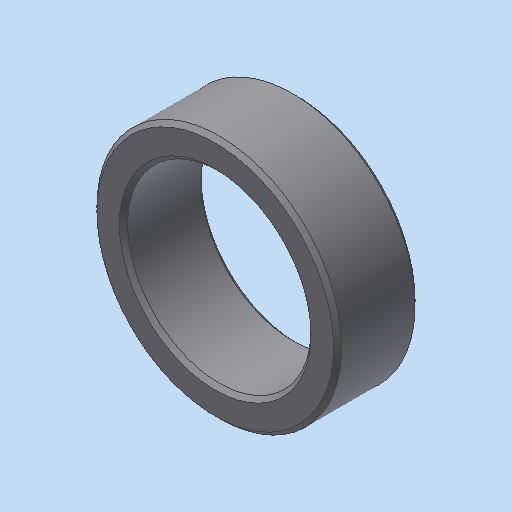
# Autodesk Inventor part: R412000671_060411_001
Saved by Autodesk Inventor 2023.3 (Build 273359000, 359)
## iProperties
Shininess: 64.0
Length Units: 11269
Angle Units: 11279
Time Units: 11290
Mass Units: 11283
Length Display Precision: 3
Angle Display Precision: 2
Compacted: True
Part Number: R412000671_060411_001
Document SubType Name: Modeling
Created: 2006-04-11
Material: Allgemein
Description: =<RBPARTNOTITLE2>
Vendor: Bosch Rexroth
Manufacturer: Standard
Standards Organization: Custom
Density: 1 g/cm^3
Mass: 0.195281 g
Surface Area: 3.47395 cm^2
Volume: 0.195281 cm^3
Appearance: Vorgabe
GAIN_REFID: 20__R412000671_060411_001:DD9CB
Control State: 0
Master: False
Checked Out: False
Ausgabe: 00
Blattnr: 000
Fläche: 0,000 mm^2
Masse: 0,000 kg
Volumen: 0,000 mm^3
RBPARTNOTITLE2: Zentrierring Ø12
RBPARTMADEOF: R039660545
RBDRAWINGMISSINGSPEC: --
AnP_Kategorie: 22
Density: 0.0
Volumn: 0.0
Area: 0.0
PropertySet Name: Model Information
Keywords: =<RBPARTMADEOF>
Comments: =<RBSURFACE2>
Revision Number: 01
Autodesk Inventor part; units mm, degrees
ref_plane "YZ Plane" through (0, 0, 0) normal (1, 0, 0) x (0, 1, 0)
ref_plane "XZ Plane" through (0, 0, 0) normal (0, 1, 0) x (-1, 0, 0)
ref_plane "XY Plane" through (0, 0, 0) normal (0, 0, 1) x (1, 0, 0)
sketch "Skizze1" plane through (0, 0, 0) normal (0, 0, 1) x (1, 0, 0)
  line L0 (-6.6, 0) -> (1.8, 0) projected
  line L1 (0, -0.4) -> (0, 5.2) projected
  line L2 (-4.5, 0) -> (-6, 0)
  line L3 (-6, 0) -> (-6, 4)
  line L4 (-6, 4) -> (-4.5, 4)
  line L5 (-4.5, 4) -> (-4.5, 0)
  point P0 (0, 0)
  dimension "d0" = 9
  dimension "d1" = 12
  dimension "d2" = 4
  constraints: 8 end point, 2 parallel, 1 horizontal, 1 perpendicular, 1 point on line
  measures "d0" diameter of L5 L1
  measures "d1" diameter of L3 L1
  measures "d2" distance of L2.end L3.end
revolve "Drehung1" add sketch "Skizze1" angle 360 about axis through (0, -10, 0) along (0, 1, 0)
chamfer "Fase1" distance 0.2 angle 45 4 edges at (6, 4, 0) (4.5, 4, 0) (6, 0, 0) (4.5, 0, 0)
